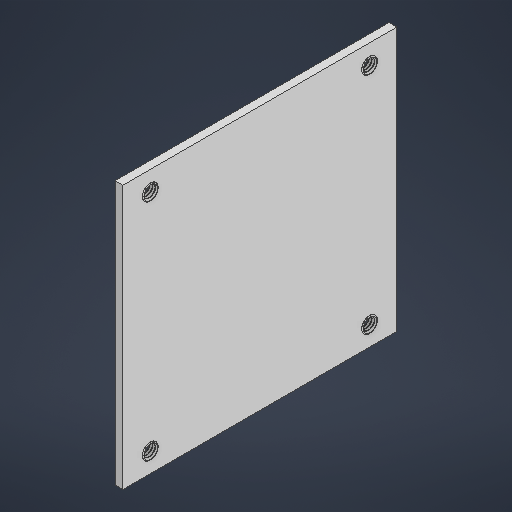
# Autodesk Inventor part: 22.10.2025-08
Saved by Autodesk Inventor 2026.1 (Build 301233020, 233B)
## iProperties
Created: 2025-12-21
Part Number: 22.10.2025-08
Material: Ogólny
Document SubType Name: Modeling
Designer: Nitro
Density: 1 g/cm^3
Appearance: Domyślna
Description: Zakrycie silnika
Author: Nitro
Autodesk Inventor part; units mm, degrees
ref_plane "YZ Plane" through (0, 0, 0) normal (1, 0, 0) x (0, 1, 0)
ref_plane "XZ Plane" through (0, 0, 0) normal (0, 1, 0) x (-1, 0, 0)
ref_plane "XY Plane" through (0, 0, 0) normal (0, 0, 1) x (1, 0, 0)
sketch "Szkic1" plane through (0, 0, 0) normal (1, 0, 0) x (0, 1, 0)
  line L0 (0, 0) -> (67.3, 0)
  line L1 (67.3, 0) -> (67.3, -70)
  line L2 (67.3, -70) -> (0, -70)
  line L3 (0, -70) -> (0, 0)
  dimension "d0" = 70
  dimension "d1" = 67.3
  constraints: 8 end point, 2 parallel, 1 horizontal, 1 perpendicular
  measures "d0" distance of L2.end L0.start
  measures "d1" distance of L1.end L2.end
extrude "Wyciągnięcie proste1" add sketch "Szkic1" along normal blind 2
sketch "Szkic2" plane through (0, 0, 0) normal (-1, 0, 0) x (0, 0, 1)
  line L0 (0, 0) -> (-70, 0) projected
  line L1 (-2, 0) -> (-2, 67.3)
  line L2 (-70, 67.3) -> (0, 67.3) projected
  line L3 (-68, 0) -> (-68, 67.3)
  line L4 (-70, 0) -> (-70, 67.3) projected
  line L5 (0, 67.3) -> (0, 0) projected
  line L6 (-2, 0) -> (-2, 10)
  line L7 (-2, 10) -> (-12, 10)
  line L8 (-12, 10) -> (-12, 0)
  line L9 (-68, 0) -> (-68, 10)
  line L10 (-68, 10) -> (-58, 10)
  line L11 (-58, 10) -> (-58, 0)
  line L12 (-58, 0) -> (-68, 0)
  line L13 (-68, 67.3) -> (-58, 67.3)
  line L14 (-58, 67.3) -> (-58, 57.3)
  line L15 (-58, 57.3) -> (-68, 57.3)
  line L16 (-68, 67.3) -> (-68, 57.3)
  line L17 (-58, 67.3) -> (-68, 67.3)
  line L18 (-2, 67.3) -> (-12, 67.3)
  line L19 (-12, 67.3) -> (-12, 57.3)
  line L20 (-12, 57.3) -> (-2, 57.3)
  point P0 (-7, 5)
  point P1 (-63, 5)
  point P2 (-63, 62.3)
  point P3 (-7, 62.3)
  dimension "d4" = 2
  dimension "d5" = 2
  dimension "d6" = 10
  dimension "d7" = 10
  dimension "d8" = 10
  dimension "d9" = 10
  dimension "d10" = 10
  dimension "d11" = 10
  dimension "d12" = 10
  dimension "d13" = 10
  dimension "d14" = 10
  constraints: 34 end point, 14 point on line, 4 perpendicular, 2 collinear, 2 vertical
  measures "d4" distance between parallel lines of L4 L3
  measures "d5" distance between parallel lines of L5 L1
  measures "d6" distance of L1.start L6.end
  measures "d7" distance of L6.end L7.end
  measures "d8" distance of L3.start L9.end
  measures "d9" distance of L9.end L10.end
  measures "d10" distance of L10.end L11.end
  measures "d11" distance of L3.end L13.end
  measures "d12" distance of L13.end L14.end
  measures "d13" distance of L1.end L18.end
  measures "d14" distance of L18.end L19.end
hole "Otwór1" at (0, 5, -7) at (0, 5, -63) at (0, 62.3, -63) at (0, 62.3, -7) direction (1, 0, 0) diameter 4 depth 6
thread "Gwint1" size "M4x0.7" class "6H" standard "ANSI Metric M Profile" full length
thread "Gwint2" size "M4x0.7" class "6H" standard "ANSI Metric M Profile" full length
thread "Gwint3" size "M4x0.7" class "6H" standard "ANSI Metric M Profile" full length
thread "Gwint4" size "M4x0.7" class "6H" standard "ANSI Metric M Profile" full length
sketch "Szkic4" plane through (0, 62.3, -7) normal (0, 1, 0) x (0, 0, 1)
  line L0 (2, 0) -> (2, 2)
  line L1 (2, 2) -> (1.481, 2)
  line L2 (1.481, 2) -> (1.481, 0)
  line L3 (1.481, 0) -> (2, 0)
  line L4 (0, -1.3161) -> (0, 2.5527) projected
  constraints: 8 end point
revolve "Obrót1" add sketch "Szkic4" angle 360 about axis through (0, 62.3, -7) along (1, 0, 0) separate body
sketch "Szkic3" plane through (0, 62.3, -5) normal (0, -1, 0) x (1, 0, 0)
  line L0 (-0.4084, -0.0356) -> (-0.3501, -0.0356) construction
  line L1 (0.0582, -0.4838) -> (-0.0001, -0.5959) construction
  line L2 (-0.7001, -0.5959) -> (-0.7584, -0.4838) construction
  line L3 (-0.2918, -0.0356) -> (-0.3501, 0.0765) construction
  line L4 (-0.3501, 0.0765) -> (-0.4084, -0.0356) construction
  line L5 (-0.7001, -0.5959) -> (-0.6418, -0.4838) construction
  line L6 (-0.2918, -0.0356) -> (-0.0584, -0.4838)
  line L7 (-0.7584, -0.4838) -> (-0.6418, -0.4838) construction
  arc A0 (-0.7584, -0.4838) -> (-0.7001, -0.5192) centre (-0.7001, -0.4534) ccw construction
  line L8 (0.0582, -0.4838) -> (-0.0584, -0.4838) construction
  line L9 (-0.7001, -0.5959) -> (-0.7001, -0.4838) construction
  line L10 (-0.0001, -0.5959) -> (-0.0001, -0.4838) construction
  line L11 (-0.3501, 0.0765) -> (-0.3501, -0.0002) construction
  line L12 (-0.7001, -0.5192) -> (-0.0001, -0.5192)
  arc A1 (-0.7001, -0.5192) -> (-0.6418, -0.4838) centre (-0.7001, -0.4534) ccw
  line L13 (-0.0584, -0.4838) -> (-0.0001, -0.5959) construction
  line L14 (-0.6418, -0.4838) -> (-0.4084, -0.0356)
  line L15 (-0.0001, -0.0002) -> (-0.0001, 0.0177)
  line L16 (-0.0001, 0.0177) -> (-0.0001, -0.0002)
  line L17 (-0.0001, -0.0002) -> (0.0334, -0.0002)
  arc A2 (-0.0584, -0.4838) -> (-0.0001, -0.5192) centre (-0.0001, -0.4534) ccw
  arc A3 (-0.0001, -0.5192) -> (0.0582, -0.4838) centre (-0.0001, -0.4534) ccw construction
  arc A4 (-0.3501, -0.0002) -> (-0.4084, -0.0356) centre (-0.3501, -0.0659) ccw
  arc A5 (-0.2918, -0.0356) -> (-0.3501, -0.0002) centre (-0.3501, -0.0659) ccw
  line L18 (-0.3501, -0.0002) -> (-0.3501, -0.0356) construction
  line L19 (-0.3501, -0.0356) -> (-0.2918, -0.0356) construction
  dimension "d30" = 55
  dimension "d31" = 0.1121
  dimension "d32" = 0.1121
  dimension "Szkic3_ThreadOffset" = 0
  dimension "Szkic3_MajorRadius" = 0.519
  dimension "d35" = 0.7
  dimension "Szkic3_MinorRadius" = 0
  constraints: 40 end point, 12 point on circle, 10 parallel, 8 tangent, 6 centre point, 6 collinear, 2 midpoint, 2 point on line, 1 horizontal, 1 perpendicular, 3 other
  measures "d30" angle of L6 L14
  measures "d31" distance of L3.end L0.end
  measures "d32" distance of L1.end L10.end
  measures "Szkic3_ThreadOffset" distance between parallel lines of L15 L10
  measures "Szkic3_MajorRadius" distance from line of L12 L15.start
  measures "d35" distance from line of L1.end L9
  measures "Szkic3_MinorRadius" distance edge to line of A5 L17
coil "Zwój1" sketch "Szkic3" operation cut axis through (0, 62.3, -7) along (1, 0, 0) pitch 0.7007 turns 4.852291 hand right bodies 2
sketch "Szkic6" plane through (0, 62.3, -63) normal (0, 1, 0) x (0, 0, 1)
  line L0 (2, 0) -> (2, 2)
  line L1 (2, 2) -> (1.481, 2)
  line L2 (1.481, 2) -> (1.481, 0)
  line L3 (1.481, 0) -> (2, 0)
  line L4 (0, -1.3627) -> (0, 2.8327) projected
  constraints: 8 end point
revolve "Obrót2" add sketch "Szkic6" angle 360 about axis through (0, 62.3, -63) along (1, 0, 0) separate body
sketch "Szkic5" plane through (0, 62.3, -61) normal (0, -1, 0) x (1, 0, 0)
  line L0 (-0.4084, -0.0356) -> (-0.3501, -0.0356) construction
  line L1 (0.0582, -0.4838) -> (-0.0001, -0.5959) construction
  line L2 (-0.7001, -0.5959) -> (-0.7584, -0.4838) construction
  line L3 (-0.2918, -0.0356) -> (-0.3501, 0.0765) construction
  line L4 (-0.3501, 0.0765) -> (-0.4084, -0.0356) construction
  line L5 (-0.7001, -0.5959) -> (-0.6418, -0.4838) construction
  line L6 (-0.2918, -0.0356) -> (-0.0584, -0.4838)
  line L7 (-0.7584, -0.4838) -> (-0.6418, -0.4838) construction
  arc A0 (-0.7584, -0.4838) -> (-0.7001, -0.5192) centre (-0.7001, -0.4534) ccw construction
  line L8 (0.0582, -0.4838) -> (-0.0584, -0.4838) construction
  line L9 (-0.7001, -0.5959) -> (-0.7001, -0.4838) construction
  line L10 (-0.0001, -0.5959) -> (-0.0001, -0.4838) construction
  line L11 (-0.3501, 0.0765) -> (-0.3501, -0.0002) construction
  line L12 (-0.7001, -0.5192) -> (-0.0001, -0.5192)
  arc A1 (-0.7001, -0.5192) -> (-0.6418, -0.4838) centre (-0.7001, -0.4534) ccw
  line L13 (-0.0584, -0.4838) -> (-0.0001, -0.5959) construction
  line L14 (-0.6418, -0.4838) -> (-0.4084, -0.0356)
  line L15 (-0.0001, -0.0002) -> (-0.0001, 0.0177)
  line L16 (-0.0001, 0.0177) -> (-0.0001, -0.0002)
  line L17 (-0.0001, -0.0002) -> (0.0334, -0.0002)
  arc A2 (-0.0584, -0.4838) -> (-0.0001, -0.5192) centre (-0.0001, -0.4534) ccw
  arc A3 (-0.0001, -0.5192) -> (0.0582, -0.4838) centre (-0.0001, -0.4534) ccw construction
  arc A4 (-0.3501, -0.0002) -> (-0.4084, -0.0356) centre (-0.3501, -0.0659) ccw
  arc A5 (-0.2918, -0.0356) -> (-0.3501, -0.0002) centre (-0.3501, -0.0659) ccw
  line L18 (-0.3501, -0.0002) -> (-0.3501, -0.0356) construction
  line L19 (-0.3501, -0.0356) -> (-0.2918, -0.0356) construction
  dimension "d48" = 55
  dimension "d49" = 0.1121
  dimension "d50" = 0.1121
  dimension "Szkic5_ThreadOffset" = 0
  dimension "Szkic5_MajorRadius" = 0.519
  dimension "d53" = 0.7
  dimension "Szkic5_MinorRadius" = 0
  constraints: 40 end point, 12 point on circle, 10 parallel, 8 tangent, 6 centre point, 6 collinear, 2 midpoint, 2 point on line, 1 horizontal, 1 perpendicular, 3 other
  measures "d48" angle of L6 L14
  measures "d49" distance of L3.end L0.end
  measures "d50" distance of L1.end L10.end
  measures "Szkic5_ThreadOffset" distance between parallel lines of L15 L10
  measures "Szkic5_MajorRadius" distance from line of L12 L15.start
  measures "d53" distance from line of L1.end L9
  measures "Szkic5_MinorRadius" distance edge to line of A5 L17
coil "Zwój2" sketch "Szkic5" operation cut axis through (0, 62.3, -63) along (1, 0, 0) pitch 0.7007 turns 4.852291 hand right bodies 3
sketch "Szkic8" plane through (0, 5, -63) normal (0, 1, 0) x (0, 0, 1)
  line L0 (2, 0) -> (2, 2)
  line L1 (2, 2) -> (1.481, 2)
  line L2 (1.481, 2) -> (1.481, 0)
  line L3 (1.481, 0) -> (2, 0)
  line L4 (0, -1.3627) -> (0, 2.8327) projected
  constraints: 8 end point
revolve "Obrót3" add sketch "Szkic8" angle 360 about axis through (0, 5, -63) along (1, 0, 0) separate body
sketch "Szkic7" plane through (0, 5, -61) normal (0, -1, 0) x (1, 0, 0)
  line L0 (-0.4084, -0.0356) -> (-0.3501, -0.0356) construction
  line L1 (0.0582, -0.4838) -> (-0.0001, -0.5959) construction
  line L2 (-0.7001, -0.5959) -> (-0.7584, -0.4838) construction
  line L3 (-0.2918, -0.0356) -> (-0.3501, 0.0765) construction
  line L4 (-0.3501, 0.0765) -> (-0.4084, -0.0356) construction
  line L5 (-0.7001, -0.5959) -> (-0.6418, -0.4838) construction
  line L6 (-0.2918, -0.0356) -> (-0.0584, -0.4838)
  line L7 (-0.7584, -0.4838) -> (-0.6418, -0.4838) construction
  arc A0 (-0.7584, -0.4838) -> (-0.7001, -0.5192) centre (-0.7001, -0.4534) ccw construction
  line L8 (0.0582, -0.4838) -> (-0.0584, -0.4838) construction
  line L9 (-0.7001, -0.5959) -> (-0.7001, -0.4838) construction
  line L10 (-0.0001, -0.5959) -> (-0.0001, -0.4838) construction
  line L11 (-0.3501, 0.0765) -> (-0.3501, -0.0002) construction
  line L12 (-0.7001, -0.5192) -> (-0.0001, -0.5192)
  arc A1 (-0.7001, -0.5192) -> (-0.6418, -0.4838) centre (-0.7001, -0.4534) ccw
  line L13 (-0.0584, -0.4838) -> (-0.0001, -0.5959) construction
  line L14 (-0.6418, -0.4838) -> (-0.4084, -0.0356)
  line L15 (-0.0001, -0.0002) -> (-0.0001, 0.0177)
  line L16 (-0.0001, 0.0177) -> (-0.0001, -0.0002)
  line L17 (-0.0001, -0.0002) -> (0.0334, -0.0002)
  arc A2 (-0.0584, -0.4838) -> (-0.0001, -0.5192) centre (-0.0001, -0.4534) ccw
  arc A3 (-0.0001, -0.5192) -> (0.0582, -0.4838) centre (-0.0001, -0.4534) ccw construction
  arc A4 (-0.3501, -0.0002) -> (-0.4084, -0.0356) centre (-0.3501, -0.0659) ccw
  arc A5 (-0.2918, -0.0356) -> (-0.3501, -0.0002) centre (-0.3501, -0.0659) ccw
  line L18 (-0.3501, -0.0002) -> (-0.3501, -0.0356) construction
  line L19 (-0.3501, -0.0356) -> (-0.2918, -0.0356) construction
  dimension "d66" = 55
  dimension "d67" = 0.1121
  dimension "d68" = 0.1121
  dimension "Szkic7_ThreadOffset" = 0
  dimension "Szkic7_MajorRadius" = 0.519
  dimension "d71" = 0.7
  dimension "Szkic7_MinorRadius" = 0
  constraints: 40 end point, 12 point on circle, 10 parallel, 8 tangent, 6 centre point, 6 collinear, 2 midpoint, 2 point on line, 1 horizontal, 1 perpendicular, 3 other
  measures "d66" angle of L6 L14
  measures "d67" distance of L3.end L0.end
  measures "d68" distance of L1.end L10.end
  measures "Szkic7_ThreadOffset" distance between parallel lines of L15 L10
  measures "Szkic7_MajorRadius" distance from line of L12 L15.start
  measures "d71" distance from line of L1.end L9
  measures "Szkic7_MinorRadius" distance edge to line of A5 L17
coil "Zwój3" sketch "Szkic7" operation cut axis through (0, 5, -63) along (1, 0, 0) pitch 0.7007 turns 4.852291 hand right bodies 4
sketch "Szkic10" plane through (0, 5, -7) normal (0, 1, 0) x (0, 0, 1)
  line L0 (2, 0) -> (2, 2)
  line L1 (2, 2) -> (1.481, 2)
  line L2 (1.481, 2) -> (1.481, 0)
  line L3 (1.481, 0) -> (2, 0)
  line L4 (0, -1.3627) -> (0, 2.8327) projected
  constraints: 8 end point
revolve "Obrót4" add sketch "Szkic10" angle 360 about axis through (0, 5, -7) along (1, 0, 0) separate body
sketch "Szkic9" plane through (0, 5, -5) normal (0, -1, 0) x (1, 0, 0)
  line L0 (-0.4084, -0.0356) -> (-0.3501, -0.0356) construction
  line L1 (0.0582, -0.4838) -> (-0.0001, -0.5959) construction
  line L2 (-0.7001, -0.5959) -> (-0.7584, -0.4838) construction
  line L3 (-0.2918, -0.0356) -> (-0.3501, 0.0765) construction
  line L4 (-0.3501, 0.0765) -> (-0.4084, -0.0356) construction
  line L5 (-0.7001, -0.5959) -> (-0.6418, -0.4838) construction
  line L6 (-0.2918, -0.0356) -> (-0.0584, -0.4838)
  line L7 (-0.7584, -0.4838) -> (-0.6418, -0.4838) construction
  arc A0 (-0.7584, -0.4838) -> (-0.7001, -0.5192) centre (-0.7001, -0.4534) ccw construction
  line L8 (0.0582, -0.4838) -> (-0.0584, -0.4838) construction
  line L9 (-0.7001, -0.5959) -> (-0.7001, -0.4838) construction
  line L10 (-0.0001, -0.5959) -> (-0.0001, -0.4838) construction
  line L11 (-0.3501, 0.0765) -> (-0.3501, -0.0002) construction
  line L12 (-0.7001, -0.5192) -> (-0.0001, -0.5192)
  arc A1 (-0.7001, -0.5192) -> (-0.6418, -0.4838) centre (-0.7001, -0.4534) ccw
  line L13 (-0.0584, -0.4838) -> (-0.0001, -0.5959) construction
  line L14 (-0.6418, -0.4838) -> (-0.4084, -0.0356)
  line L15 (-0.0001, -0.0002) -> (-0.0001, 0.0177)
  line L16 (-0.0001, 0.0177) -> (-0.0001, -0.0002)
  line L17 (-0.0001, -0.0002) -> (0.0334, -0.0002)
  arc A2 (-0.0584, -0.4838) -> (-0.0001, -0.5192) centre (-0.0001, -0.4534) ccw
  arc A3 (-0.0001, -0.5192) -> (0.0582, -0.4838) centre (-0.0001, -0.4534) ccw construction
  arc A4 (-0.3501, -0.0002) -> (-0.4084, -0.0356) centre (-0.3501, -0.0659) ccw
  arc A5 (-0.2918, -0.0356) -> (-0.3501, -0.0002) centre (-0.3501, -0.0659) ccw
  line L18 (-0.3501, -0.0002) -> (-0.3501, -0.0356) construction
  line L19 (-0.3501, -0.0356) -> (-0.2918, -0.0356) construction
  dimension "d84" = 55
  dimension "d85" = 0.1121
  dimension "d86" = 0.1121
  dimension "Szkic9_ThreadOffset" = 0
  dimension "Szkic9_MajorRadius" = 0.519
  dimension "d89" = 0.7
  dimension "Szkic9_MinorRadius" = 0
  constraints: 40 end point, 12 point on circle, 10 parallel, 8 tangent, 6 centre point, 6 collinear, 2 midpoint, 2 point on line, 1 horizontal, 1 perpendicular, 3 other
  measures "d84" angle of L6 L14
  measures "d85" distance of L3.end L0.end
  measures "d86" distance of L1.end L10.end
  measures "Szkic9_ThreadOffset" distance between parallel lines of L15 L10
  measures "Szkic9_MajorRadius" distance from line of L12 L15.start
  measures "d89" distance from line of L1.end L9
  measures "Szkic9_MinorRadius" distance edge to line of A5 L17
coil "Zwój4" sketch "Szkic9" operation cut axis through (0, 5, -7) along (1, 0, 0) pitch 0.7007 turns 4.852291 hand right bodies 5
equation "\"d30\" = d37"
equation "\"d31\" = 0.160083 * Szkic3_Pitch"
equation "\"d32\" = 0.160083 * Szkic3_Pitch"
equation "\"d35\" = Szkic3_Pitch"
equation "\"d48\" = d55"
equation "\"d49\" = 0.160083 * Szkic5_Pitch"
equation "\"d50\" = 0.160083 * Szkic5_Pitch"
equation "\"d53\" = Szkic5_Pitch"
equation "\"d66\" = d73"
equation "\"d67\" = 0.160083 * Szkic7_Pitch"
equation "\"d68\" = 0.160083 * Szkic7_Pitch"
equation "\"d71\" = Szkic7_Pitch"
equation "\"d84\" = d91"
equation "\"d85\" = 0.160083 * Szkic9_Pitch"
equation "\"d86\" = 0.160083 * Szkic9_Pitch"
equation "\"d89\" = Szkic9_Pitch"
equation "\"d37\" = 55deg"
equation "\"Szkic3_Pitch\" = 0.7"
equation "\"d55\" = 55deg"
equation "\"Szkic5_Pitch\" = 0.7"
equation "\"d73\" = 55deg"
equation "\"Szkic7_Pitch\" = 0.7"
equation "\"d91\" = 55deg"
equation "\"Szkic9_Pitch\" = 0.7"
